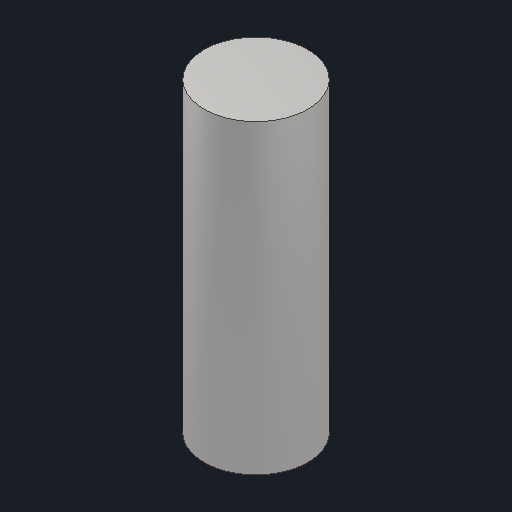
# Autodesk Inventor part: tripod_leg_tube
Saved by Autodesk Inventor 2027.1 (Build 311270010, 270A)
## iProperties
Created: 2026-11-04
Part Number: tripod_leg_tube
Material: Generic
Description: 2 in stainless tripod leg (shown cut short)
Document SubType Name: Modeling
Designer: Claude (from photos)
Density: 1 g/cm^3
Appearance: Stainless - Satin
Author: alexg
Autodesk Inventor part; units mm, degrees
ref_plane "YZ Plane" through (0, 0, 0) normal (1, 0, 0) x (0, 1, 0)
ref_plane "XY Plane" through (0, 0, 0) normal (0, 0, 1) x (1, 0, 0)
ref_plane "Work Plane1" through (0, -130, 0) normal (0, 1, 0) x (-1, 0, 0)
sketch "Leg tube 2in (cut short) sketch" plane through (0, -130, 0) normal (0, 1, 0) x (-1, 0, 0)
  circle A0 centre (0, 0) radius 25.4
  constraints: 1 centre point
extrude "Leg tube 2in (cut short)" add sketch "Leg tube 2in (cut short) sketch" against normal blind 150
body "Solid1"
